MOD-GRID Prybar Holder (Autodesk Fusion 360 design; units mm, degrees)
part number: 2026-10-24-09-23-08-234
Autodesk Fusion 360 part; units mm, degrees
ref_plane "WorkPlane114" through (36, 0, 0) normal (1, 0, 0) x (0, 1, 0)
sketch "Bar blank" plane through (36, 0, 0) normal (1, 0, 0) x (0, 0, -1)
  line L0 (-5.5, -3) -> (-11.5, -3)
  line L1 (-11.5, -3) -> (-11.5, 3)
  line L2 (-11.5, 3) -> (-5.5, 3)
  line L3 (-5.5, 3) -> (-5.5, -3)
extrude "Extrude216" add sketch "Bar blank" along normal blind 36 and the other way blind 36 makes body 1
sketch "Bar wedge" plane through (0, 0, 0) normal (0, 1, 0) x (1, 0, 0)
  line L0 (55, -11.5) -> (72, -6)
  line L1 (72, -6) -> (74, -6)
  line L2 (74, -6) -> (74, -12.5)
  line L3 (74, -12.5) -> (55, -12.5)
  line L4 (55, -12.5) -> (55, -11.5)
extrude "Extrude217" cut sketch "Bar wedge" along normal blind 6 and the other way blind 6 bodies 1
sketch "Bar lanyard slot" plane through (0, 0, 0) normal (0, 1, 0) x (1, 0, 0)
  arc A0 (2.5, -7) -> (2, -7.5) centre (2.5, -7.5) ccw
  arc A1 (8.5, -7.5) -> (8, -7) centre (8, -7.5) ccw
  arc A2 (8, -10) -> (8.5, -9.5) centre (8, -9.5) ccw
  arc A3 (2, -9.5) -> (2.5, -10) centre (2.5, -9.5) ccw
  line L0 (2.5, -7) -> (8, -7)
  line L1 (8.5, -7.5) -> (8.5, -9.5)
  line L2 (8, -10) -> (2.5, -10)
  line L3 (2, -9.5) -> (2, -7.5)
extrude "Extrude218" cut sketch "Bar lanyard slot" along normal blind 6 and the other way blind 6 bodies 1
fillet "Fillet59" radius 0.5 4 edges at (27.5, -3, 11.5) (36, -3, 5.5) (36, 3, 5.5) (27.5, 3, 11.5) on bodies 1
ref_plane "WorkPlane115" through (17, 0, 0) normal (1, 0, 0) x (0, 1, 0)
sketch "Clip body" plane through (17, 0, 0) normal (1, 0, 0) x (0, 0, -1)
  line L0 (0, -10.6) -> (-13.518, -10.6)
  line L1 (-13.518, -10.6) -> (-13.518, 10.6)
  line L2 (-13.518, 10.6) -> (0, 10.6)
  line L3 (0, 10.6) -> (0, -10.6)
extrude "Extrude219" add sketch "Clip body" along normal blind 6 and the other way blind 6 separate body makes body 2
fillet "Fillet60" radius 1.5 4 edges at (17, 10.6, 0) (17, -10.6, 0) (17, -10.6, 13.518) (17, 10.6, 13.518) on bodies 2
sketch "Clip cavity" plane through (17, 0, 0) normal (1, 0, 0) x (0, 0, -1)
  arc A0 (-5.5, 3.5) -> (-6, 4) centre (-6, 3.5) ccw
  arc A1 (-12.718, 4) -> (-10.558, 4) centre (-11.638, 4) ccw
  line L0 (-6, 4) -> (-10.558, 4)
  line L1 (-12.718, 4) -> (-15.518, 4)
  arc A2 (-6, -4) -> (-5.5, -3.5) centre (-6, -3.5) ccw
  arc A3 (-10.558, -4) -> (-12.718, -4) centre (-11.638, -4) ccw
  line L2 (-6, -4) -> (-10.558, -4)
  line L3 (-12.718, -4) -> (-15.518, -4)
  line L4 (-5.5, -3.5) -> (-5.5, 3.5)
  line L5 (-15.518, -4) -> (-15.518, 4)
extrude "Extrude220" cut sketch "Clip cavity" along normal blind 12 and the other way blind 12 bodies 2
sketch "Clip relief" plane through (17, 0, 0) normal (1, 0, 0) x (0, 0, -1)
  arc A0 (-3.3717, 2.2744) -> (-6, 6.4) centre (-6, 3.5) ccw
  arc A1 (-2.2841, 1.7673) -> (-6, 7.6) centre (-6, 3.5) ccw
  line L0 (-6, 6.4) -> (-7.5, 5.6)
  line L1 (-7.5, 5.6) -> (-15.518, 5.6)
  line L2 (-15.518, 5.6) -> (-15.518, 7.6)
  line L3 (-15.518, 7.6) -> (-6, 7.6)
  line L4 (-2.2841, 1.7673) -> (-3.3717, 2.2744)
  circle A2 centre (-2.8279, 2.0208) radius 0.6
  arc A3 (-6, -6.4) -> (-3.3717, -2.2744) centre (-6, -3.5) ccw
  arc A4 (-6, -7.6) -> (-2.2841, -1.7673) centre (-6, -3.5) ccw
  line L5 (-6, -6.4) -> (-7.5, -5.6)
  line L6 (-7.5, -5.6) -> (-15.518, -5.6)
  line L7 (-15.518, -5.6) -> (-15.518, -7.6)
  line L8 (-15.518, -7.6) -> (-6, -7.6)
  line L9 (-2.2841, -1.7673) -> (-3.3717, -2.2744)
  circle A5 centre (-2.8279, -2.0208) radius 0.6
extrude "Extrude221" cut sketch "Clip relief" along normal blind 12 and the other way blind 12 bodies 2
chamfer "Chamfer52" distance 0.5 angle 45 16 edges at (11, 8.35, 13.518) (11, 10.1607, 13.0787) (11, 10.6, 6.759) (11, 10.1607, 0.4393) (11, 0, 0) (11, -10.1607, 0.4393) (11, -10.6, 6.759) (11, -10.1607, 13.0787) (11, -8.35, 13.518) (11, -4.8, 13.518) (11, -4, 8.279) (11, -3.8536, 5.6464) (11, 0, 5.5) (11, 3.8536, 5.6464) (11, 4, 8.279) (11, 4.8, 13.518) tangent chain off on bodies 2
ref_plane "WorkPlane116" through (11, 0, 0) normal (1, 0, 0) x (0, 1, 0)
sketch "Clip legs" plane through (11, 0, 0) normal (1, 0, 0) x (0, 0, -1)
  line L0 (-0.5, -5.45) -> (4.64, -5.45)
  line L1 (4.64, -5.45) -> (4.64, -5.93)
  line L2 (4.64, -5.93) -> (3.4, -7.19)
  line L3 (3.4, -7.19) -> (3.1, -6.32)
  line L4 (3.1, -6.32) -> (-0.5, -6.32)
  line L5 (-0.5, -6.32) -> (-0.5, -5.45)
  line L6 (-0.5, -2.55) -> (4.64, -2.55)
  line L7 (4.64, -2.55) -> (4.64, -2.07)
  line L8 (4.64, -2.07) -> (3.4, -0.81)
  line L9 (3.4, -0.81) -> (3.1, -1.68)
  line L10 (3.1, -1.68) -> (-0.5, -1.68)
  line L11 (-0.5, -1.68) -> (-0.5, -2.55)
  line L12 (-0.5, 2.55) -> (4.64, 2.55)
  line L13 (4.64, 2.55) -> (4.64, 2.07)
  line L14 (4.64, 2.07) -> (3.4, 0.81)
  line L15 (3.4, 0.81) -> (3.1, 1.68)
  line L16 (3.1, 1.68) -> (-0.5, 1.68)
  line L17 (-0.5, 1.68) -> (-0.5, 2.55)
  line L18 (-0.5, 5.45) -> (4.64, 5.45)
  line L19 (4.64, 5.45) -> (4.64, 5.93)
  line L20 (4.64, 5.93) -> (3.4, 7.19)
  line L21 (3.4, 7.19) -> (3.1, 6.32)
  line L22 (3.1, 6.32) -> (-0.5, 6.32)
  line L23 (-0.5, 6.32) -> (-0.5, 5.45)
extrude "Extrude222" add sketch "Clip legs" along normal blind 4.76 bodies 2
ref_plane "WorkPlane117" through (66.9, 0, 0) normal (1, 0, 0) x (0, 1, 0)
sketch "Nose body" plane through (66.9, 0, 0) normal (1, 0, 0) x (0, 0, -1)
  line L0 (0, -10.6) -> (-12.506, -10.6)
  line L1 (-12.506, -10.6) -> (-12.506, 10.6)
  line L2 (-12.506, 10.6) -> (0, 10.6)
  line L3 (0, 10.6) -> (0, -10.6)
extrude "Extrude223" add sketch "Nose body" along normal blind 7.9 and the other way blind 7.9 separate body makes body 3
fillet "Fillet61" radius 1.5 4 edges at (66.9, 10.6, 0) (66.9, -10.6, 0) (66.9, -10.6, 12.506) (66.9, 10.6, 12.506) on bodies 3
sketch "Nose cavity" plane through (0, 0, 0) normal (0, 1, 0) x (1, 0, 0)
  line L0 (58, -5.15) -> (72.3, -5.15)
  line L1 (72.3, -5.15) -> (72.3, -6.8)
  line L2 (72.3, -6.8) -> (72, -6.8)
  line L3 (72, -6.8) -> (58, -11.3294)
  line L4 (58, -11.3294) -> (58, -5.15)
extrude "Extrude224" cut sketch "Nose cavity" along normal blind 4.1 and the other way blind 4.1 bodies 3
chamfer "Chamfer53" distance 0.5 angle 45 12 edges at (59, -4.1, 8.0779) (59, 0, 5.15) (59, 4.1, 8.0779) (59, 0, 11.0059) (59, 10.1607, 12.0667) (59, 0, 12.506) (59, -10.1607, 12.0667) (59, -10.6, 6.253) (59, -10.1607, 0.4393) (59, 0, 0) (59, 10.1607, 0.4393) (59, 10.6, 6.253) tangent chain off on bodies 3
ref_plane "WorkPlane118" through (59, 0, 0) normal (1, 0, 0) x (0, 1, 0)
sketch "Nose legs" plane through (59, 0, 0) normal (1, 0, 0) x (0, 0, -1)
  line L0 (-0.5, -5.45) -> (4.64, -5.45)
  line L1 (4.64, -5.45) -> (4.64, -5.93)
  line L2 (4.64, -5.93) -> (3.4, -7.19)
  line L3 (3.4, -7.19) -> (3.1, -6.32)
  line L4 (3.1, -6.32) -> (-0.5, -6.32)
  line L5 (-0.5, -6.32) -> (-0.5, -5.45)
  line L6 (-0.5, -2.55) -> (4.64, -2.55)
  line L7 (4.64, -2.55) -> (4.64, -2.07)
  line L8 (4.64, -2.07) -> (3.4, -0.81)
  line L9 (3.4, -0.81) -> (3.1, -1.68)
  line L10 (3.1, -1.68) -> (-0.5, -1.68)
  line L11 (-0.5, -1.68) -> (-0.5, -2.55)
  line L12 (-0.5, 2.55) -> (4.64, 2.55)
  line L13 (4.64, 2.55) -> (4.64, 2.07)
  line L14 (4.64, 2.07) -> (3.4, 0.81)
  line L15 (3.4, 0.81) -> (3.1, 1.68)
  line L16 (3.1, 1.68) -> (-0.5, 1.68)
  line L17 (-0.5, 1.68) -> (-0.5, 2.55)
  line L18 (-0.5, 5.45) -> (4.64, 5.45)
  line L19 (4.64, 5.45) -> (4.64, 5.93)
  line L20 (4.64, 5.93) -> (3.4, 7.19)
  line L21 (3.4, 7.19) -> (3.1, 6.32)
  line L22 (3.1, 6.32) -> (-0.5, 6.32)
  line L23 (-0.5, 6.32) -> (-0.5, 5.45)
extrude "Extrude225" add sketch "Nose legs" along normal blind 4.76 bodies 3
equation "bar_w = 6.0 mm" comment "ESTIMATE from photos. Bar width, the dimension ACROSS the plate. The clip pinches this, so it is the one measurement that must be right."
equation "bar_t = 6.0 mm" comment "ESTIMATE from photos. Bar thickness, the dimension standing off the plate."
equation "bar_len = 72.0 mm" comment "ESTIMATE from photos (readings spread 65-73 depending on parallax). Only sets where the two bodies sit."
equation "taper_len = 28.0 mm" comment "ESTIMATE from photos. Length of the tapered pry tip measured back from the point. The socket is kept clear of it so it grips full section."
equation "cav_clear = 2.00 mm + 2 * fit_adj" comment "Clearance added to the cavity WIDTH (total, so 0.15/side). The seat is a slip fit; the throat above it is the interference."
equation "arm_spread = 0.60 mm" comment "TOTAL pinch interference: the throat is this much narrower than the bar. Same value as the pen clip. Each arm deflects half of it."
equation "cav_hw = ( bar_w + cav_clear ) / 2" comment "Seat half width"
equation "throat_hw = bar_w / 2 - arm_spread / 2" comment "Throat half width - narrower than the bar, this is the grip"
equation "base_t = 5.5 mm" comment "Base under the bar. Also sets the WEB under the relief slot root; raising it lifts cavity and slot together so it costs no arm stress. Keep the web >= 1.0 mm."
equation "grip_h = 3.0 mm" comment "Height of the full-width seat. The throat starts here, so the arms hug the bar's lower grip_h. Keep well under bar_t: clip_h - base_t is how far the square end must descend, and that drives the tilt the socket has to allow."
equation "land_h = 0.8 mm" comment "Arm height above the throat start"
equation "cav_r = 0.5 mm" comment "Seat bottom corner radius - also the arc the relief slot follows"
equation "arm_t = 1.6 mm" comment "CONSTANT arm thickness, 3 perimeters at 0.4"
equation "relief_w = 1.2 mm" comment "Relief slot width behind the arm"
equation "relief_a0 = -115 deg" comment "Relief slot root angle about the seat corner centre, measured from +Y. Past -90 the slot tucks UNDER the seat floor, which is what buys the arm its length. More negative = longer, softer arm, but watch the web."
equation "rail_t = 3.0 mm" comment "Outer rail beyond the relief slot"
equation "throat_cham = 0.4 mm" comment "Lead-in chamfer at the top of the throat. SMALL: the arm is thinnest at its tip and a big ramp feathers it to nothing (the Zippo lesson)."
equation "clip_len = 12.0 mm" comment "Clip length along the bar = part height when printed"
equation "clip_h = bead_z + bead_r + land_h" comment "Clip overall height"
equation "body_hw = cav_hw + arm_root + relief_w + rail_t" comment "Half width, shared by both bodies so they look like a set"
equation "slv_len = 8.0 mm" comment "Socket length along the bar. SHORT on purpose - with headroom it sets the tilt budget for swinging the square end down."
equation "sleeve_hr = 2.5 mm" comment "Headroom above the bar inside the socket. This is the tilt allowance, not slop: the bar rests on the socket floor and the clip holds it there."
equation "slv_roof = 1.5 mm" comment "Material above the tunnel"
equation "slv_h = base_t + bar_t + sleeve_hr + slv_roof" comment "Socket overall height"
equation "clip_x0 = 11.0 mm" comment "Clip bed face. The bar's square end sticks out this far - the finger grab for lifting it."
equation "slv_cells = 3" comment "Whole grid cells between the two bodies' leg rows. Set by run() so the socket clears the taper; both parts must land on the same 8 mm grid."
equation "grid_pitch = 8 mm" comment "MOD-GRID pitch"
equation "slv_x0 = clip_x0 + slv_cells * grid_pitch" comment "Socket bed face = its mouth, facing the clip"
equation "body_corner_r = 1.5 mm" comment "Rounded outer corners"
equation "first_layer_cham = 0.5 mm" comment "Elephant-foot chamfer on the bed face"
equation "leg_pair_y = 4.0 mm" comment "Leg pairs at +/- this; 8 mm apart = 1 cell"
equation "leg_clear = 0.14 mm" comment "Shrinks the leg LENGTH and SHANK (not the barb). MEASURED: this printer runs 0.07 per wall, so a hole comes out 0.14 under and an external feature 0.14 over. Zero it if the printer is calibrated."
equation "leg_hole_len = 4.90 mm - leg_clear" comment "Leg extent along the print axis"
equation "leg_inner_hw = 1.45 mm" comment "Leg inner face from pair centre -> 2.90 gap"
equation "leg_shank_hw = 2.39 mm - leg_clear / 2" comment "Relaxed shank half-span"
equation "barb_hw = 3.19 mm" comment "Barb peak half-span. NOT reduced by leg_clear - the barb is meant to squeeze elastically."
equation "barb_z = -3.40 mm" comment "Barb peak depth below the seating face"
equation "catch_z = -3.10 mm" comment "Catch face: 0.10 below the 3.00 plate"
equation "leg_tip_z = -4.64 mm" comment "Leg tip"
equation "leg_tip_hw = 2.00 mm - leg_clear / 2" comment "Tip half-span, sets the ~45 deg lead-in"
equation "tip_w = 3.0 mm" comment "ESTIMATE from photos. Width at the very point."
equation "bevel_len = 12.0 mm" comment "ESTIMATE from photos. Length of the chisel bevel on the top face, back from the point. SHORTER than taper_len - photo 4 shows the thickness only breaking near the tip while the width narrows much further back."
equation "tip_t = 0.5 mm" comment "ESTIMATE from photos. Thickness at the very point. This one drives the socket chamber height: the thinner the tip, the less the chamber has to be raised to let the bar swing."
equation "nose_len = 15.800 mm" comment "Nose cap length. SHORT and right at the point: it is the pivot the bar swings about, so the further out it sits the longer the lever to the clip and the smaller the tilt needed."
equation "nose_wclear = 2.20 mm + 2 * fit_adj" comment "Width clearance at the nose mouth (total). The bar keeps narrowing inside, so clearance only grows."
equation "nose_drop = 2.80 mm" comment "Cavity floor BELOW the seated height. This is the one that makes the swing possible: tilted square-end-up, the point dips below where it finally sits, and a floor at the seated height would simply block it."
equation "nose_rise = 1.00 mm" comment "Cavity ceiling above the bar's top face at the mouth"
equation "nose_sec_w = 6.000 mm" comment "Bar WIDTH where the nose mouth sits - DERIVED by run() from taper_len/tip_w, not an independent number. Shown as a parameter so the fit is inspectable."
equation "nose_sec_t = 4.706 mm" comment "Bar THICKNESS where the nose mouth sits - DERIVED by run() from bevel_len/tip_t."
equation "sock_end_t = 2.5 mm" comment "Closed end capping the point. Printed standing on the mouth this is a ceiling bridged over the cavity - a short span, fine."
equation "nose_roof = 1.5 mm" comment "Material above the cavity"
equation "nose_h = base_t + nose_sec_t + nose_top_clear + nose_roof" comment "Nose overall height"
equation "nose_cells = 6" comment "Whole grid cells between the two bodies' leg rows. Set by run() to push the nose as far toward the point as the bar allows; both parts must land on the same 8 mm grid."
equation "nose_x0 = clip_x0 + nose_cells * grid_pitch" comment "Nose bed face = its mouth, facing the clip"
equation "nose_x1 = nose_x0 + nose_len" comment "Nose blind end - past the point, so the wedge is captive"
equation "wedge_x = 55.0 mm" comment "MEASURED. Where the wedge begins, from the square end. The bar is a constant 6 mm square up to here - there is NO width taper (what looked like one in the photos was the wedge face seen foreshortened)."
equation "wedge_len = bar_len - wedge_x" comment "Wedge length"
equation "hole_x = 2.0 mm" comment "MEASURED. Near edge of the lanyard slot, from the square end."
equation "hole_len = 6.5 mm" comment "MEASURED. Slot length along the bar -> it runs x 2.0..8.5."
equation "hole_inset = 1.5 mm" comment "MEASURED. Slot edge to the top and bottom faces, so the slot is bar_t - 2*hole_inset = 3.0 tall."
equation "hole_r = 0.5 mm" comment "MEASURED corner radius. Tiny - if this was meant to be 0.5 it changes nothing but the reference body."
equation "bar_edge_r = 0.5 mm" comment "MEASURED. R0.5 on the whole bar. On the cross-section this leaves the side faces flat only between z 4.5 and 9.5, and the TOP FACE only 5.0 wide - which is why the capture lip has to reach 0.8 mm in to get a worthwhile bite."
equation "lip_over = 0.08 mm" comment "How far each lip reaches inboard of the bar's side face. This IS the capture: the bar cannot rise without splaying each arm by this much. 0.8 puts the lip tip 0.3 mm over the flat top face, clear of the R0.5 corner and clear of the printer's 0.07/wall bias."
equation "lip_flat = 0.40 mm" comment "Flat on the lip tip. A knife edge is not printable; 0.4 is one nozzle width."
equation "lip_tip_y = bar_w / 2 - lip_over" comment "Lip tip, inboard of the bar's side face"
equation "lip_z = base_t + bar_t" comment "Lip underside sits on the bar's top face"
equation "bead_r = cav_hw - lip_tip_y" comment "Bead radius. Equal to the reach by construction, which makes the bead a HALF CIRCLE tangent to the cavity wall at both ends - no tooth, no tip, no corner anywhere on the arm. A pointed lip between two 45 deg ramps leaves a 0.4 mm feature on a 1.2 mm arm and snaps off; this is a local thickening instead."
equation "bead_clear = 0.05 mm" comment "Clearance between the bead and the bar's top corner radius when seated"
equation "bead_z = 11.638 mm" comment "Bead centre height - DERIVED by run() as the lowest the bead can sit without fouling the bar's R0.5 top corner. Raising the bead also lengthens the arm, which is why the margin improved when the tooth went."
equation "nose_floor_clear = 0.35 mm + fit_adj" comment "Cavity floor below the seated height. Near zero: the bar's underside is FLAT for its whole length (the wedge is on one face only), so the nose floor and the clip floor are the same plane and the bar is supported at both ends."
equation "nose_top_clear = 0.80 mm + fit_adj" comment "Clearance over the wedge face. The cavity ceiling runs at the SAME slope as the wedge, so this clearance is constant along the pocket - the bar slides in parallel and stops on the blind face rather than jamming."
equation "tip_gap = 0.30 mm" comment "Air between the point and the blind face. Small, because this is the axial stop that positions the bar."
equation "arm_root = 2.4 mm" comment "Arm thickness AT THE ROOT = 6 extrusions at 0.4. The arm is TAPERED - thick at the base, thinner at the tip - because the bending moment is largest at the root and zero at the bead. A thick root also pushes the relief slot outboard, which is what gives the ROOT WEB its thickness. The 1.2 mm version that broke on first insertion was anchored on a 0.162 mm ligament; that, not bending, is what failed."
equation "arm_tip = 1.6 mm" comment "Arm thickness at the bead = 4 extrusions. Never below 4: 1.2 mm is 2.86 extrusions and the slicer lays a gap-fill bond line down the middle of the flexure."
equation "arm_blend = 1.5 mm" comment "Height above the cavity corner over which arm_root blends down to arm_tip. A step would be a stress riser; blending keeps the thick material where the moment is and leaves the rest compliant."
equation "fit_adj = 0.00 mm" comment "ONE KNOB for every surface the bar touches: the clip cavity, the nose width, the nose floor and the nose roof all carry it, per side. It exists because this part has now failed to fit twice for the same reason - a clearance that was corrected in one pocket and not the other - and chasing four numbers is what caused that. Raise it if the PRINTER runs tighter than the assumed 0.07/wall; if instead the BAR is bigger than bar_w/bar_t, fix those and leave this at zero, because they also move the bead, the reference body and the nose section."
equation "d1242 = bar_len / 2"
equation "d1244 = bar_len / 2"
equation "d1246 = bar_len / 2"
equation "d1248 = bar_w"
equation "d1250 = bar_w"
equation "d1252 = bar_w"
equation "d1254 = bar_w"
equation "d1257 = bar_edge_r"
equation "d1258 = clip_x0 + clip_len / 2"
equation "d1260 = clip_len / 2"
equation "d1262 = clip_len / 2"
equation "d1265 = body_corner_r"
equation "d1266 = clip_len"
equation "d1268 = clip_len"
equation "d1270 = clip_len"
equation "d1272 = clip_len"
equation "d1274 = first_layer_cham"
equation "d1275 = clip_x0"
equation "d1277 = leg_hole_len"
equation "d1279 = ( nose_x0 + nose_x1 ) / 2"
equation "d1281 = nose_len / 2"
equation "d1283 = nose_len / 2"
equation "d1286 = body_corner_r"
equation "d1287 = ( bar_w + nose_wclear ) / 2"
equation "d1289 = ( bar_w + nose_wclear ) / 2"
equation "d1291 = first_layer_cham"
equation "d1292 = nose_x0"
equation "d1294 = leg_hole_len"
named bodies: "Reference - Mighty Bar", "End Clip", "Tip Nose"
